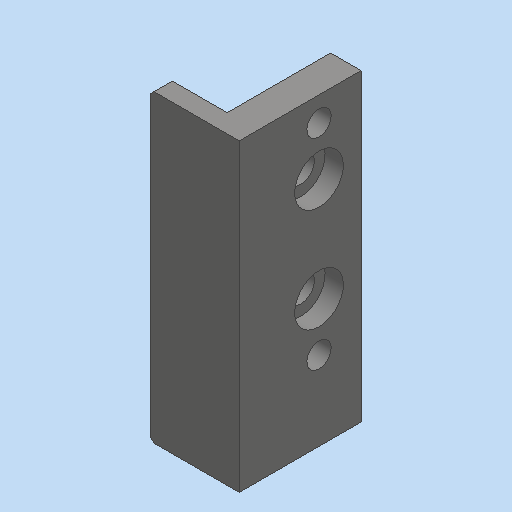
# Autodesk Inventor part: MM0948AN120_G01_108
Saved by Autodesk Inventor 2023.3 (Build 273359000, 359)
## iProperties
RuleStatus: InUse
Created: 2023-03-23
Part Number: MM0948AN120_G01_108
Material: 1.2379 X155CrVMo12-1
Description: =<RBPARTNOTITLE2>
Document SubType Name: Modeling
Designer: FH/Wi
Mass: 49.5555 g
Surface Area: 39.1104 cm^2
Volume: 6.3128 cm^3
Density: 7.85 g/cm^3
Appearance: Stahl - rostfrei AnP
AnP_Kategorie: 1
AnP_Material: =<Material>
MaxAbmaße: 50 x 20 x 14,5 (FM)
AnP_TemplVers: 20200821
RBDOCUMENTTYPE: DRF
RBDOCUMENTVERSION: 00
RBDRAWINGMAINSCALE: 1:1
RBDRAWINGMISSINGSPEC: --
RBDRAWINGVOLUME: --
RBDSV1: 0850
RBGBEDGESIN1: +0,5
RBGBEDGESIN2: +0,2
RBGBEDGESOUT1: -0,3
RBGBEDGESOUT2: -0,1
RBMATERIAL: =<Material>
RBMATMEETS: --
RBMATNO: =<Part Number>
RBPARTMADEOF: 50 x 20 x 14,5 (FM)
RBPARTNO: SIEHE MNR
RBPARTNOTITLE1: manufactured part
RBPARTNOTITLE2: Anfertigungsteil
RBPARTSAFETYINDICATOR: --
RBSURFACE: plasma nitrided 1000 HV, Nht 0,1 + 0,1
RBSURFACE2: plasmanitriert 1000 HV, Nht 0,1 + 0,1
RBZEDGESNORM: ISO13715:2002-06
RBZGENDIMCLASS: m
RBZGENDIMNORM: ISO 2768-1:1989-11
RBZGENGEOCLASS: H
RBZGENGEONORM: ISO 2768-2:1989-11
RBZSURFACENORM: ISO13D2:2002-02
RBZTOLERANCENORM: ISO 14405-1:2010-12
AnP_Kommentar_aktuell: =<Comments>
AnP_Material_aktuell: =<Material>
Author: FH/Wi
Keywords: =<RBPARTMADEOF>
Comments: =<RBSURFACE2>
Revision Number: 01
Autodesk Inventor part; units mm, degrees
ref_plane "YZ Plane" through (0, 0, 0) normal (1, 0, 0) x (0, 1, 0)
ref_plane "XZ Plane" through (0, 0, 0) normal (0, 1, 0) x (-1, 0, 0)
ref_plane "XY Plane" through (0, 0, 0) normal (0, 0, 1) x (1, 0, 0)
sketch "Skizze1" plane through (0, 0, 0) normal (0, 0, 1) x (1, 0, 0)
  line L0 (0, 20) -> (-5, 20)
  line L1 (-14.5, 3.9) -> (-14.5, 0)
  line L2 (-14.5, 0) -> (0, 0)
  line L3 (0, 0) -> (0, 20)
  line L4 (-14.5, 3.9) -> (-5, 3.9)
  line L5 (-5, 3.9) -> (-5, 20)
  dimension "d0" = 3.9
  dimension "d1" = 14.5
  dimension "d2" = 5
  dimension "d3" = 20
  constraints: 12 end point, 2 horizontal, 2 parallel, 2 perpendicular, 1 coincident
  measures "d0" distance of L1.start L1.end
  measures "d1" distance of L1.end L2.end
  measures "d2" distance of L0.start L0.end
  measures "d3" distance of L2.end L0.start
extrude "Extrusion1" add sketch "Skizze1" along normal mid plane 50
chamfer "Fase1" distance 5 angle 10 1 edges at (-9.75, 3.9, 25) measured on face at (-8.1667, 3.9, -8.3333)
chamfer "Fase2" distance 5 angle 10 1 edges at (-9.75, 3.9, -25) measured on face at (-8.1667, 3.9, -10)
chamfer "Fase3" distance 0.5 angle 45 5 edges at (-14.5, 1.5092, 25) (-14.5, 3.4592, 22.5) (-14.5, 3.9, 0) (-14.5, 3.4592, -22.5) (-14.5, 1.5092, -25)
sketch "Skizze3" plane through (0, 0, 25) normal (1, 0, 0) x (0, 0, -1)
  line L0 (50, 20) -> (0, 20) projected
  line L1 (25, -4) -> (25, 24) projected
  point P0 (25, 0)
  point P1 (4, 13.1)
  point P2 (37, 13.1)
  dimension "d24" = 6.9
  dimension "d33" = 21
  dimension "d34" = 12
  constraints: 1 horizontal alignment
  measures "d24" distance from line of L0 point (4, 13.1)
  measures "d33" distance from line of L1 point (4, 13.1)
  measures "d34" distance from line of L1 point (37, 13.1)
hole "Bohrung2" at (0, 13.1, 21) at (0, 13.1, -12) direction (-1, 0, 0) diameter 4 end through all
sketch "Skizze4" plane through (0, 0, 25) normal (1, 0, 0) x (0, 0, -1)
  circle A0 centre (4, 13.1) radius 2 projected
  point P0 (25, 0)
  point P1 (12, 13.1)
  point P2 (29, 13.1)
  dimension "d35" = 8
  dimension "d36" = 17
  constraints: 2 horizontal alignment
  measures "d35" distance of point (12, 13.1) A0.centre
  measures "d36" distance of point (29, 13.1) point (12, 13.1)
hole "Bohrung3" at (0, 13.1, 13) at (0, 13.1, -4) direction (-1, 0, 0) diameter 4.5 end through all counterbore diameter 8 counterbore depth 3 clearance for "Flachk.Schr. DIN 6912  versenkt" size "M4" standard "ISO"
equation "\"d9\" = d6"
equation "\"d11\" = d8"
equation "\"d23\" = d8"
equation "\"d6\" = 5"
equation "\"d8\" = 10deg"
